Autodesk Inventor part; units mm, degrees
(part 2 of 2)
  line L179 (40.3047, 40.3055) -> (37.6531, 37.6538) construction
  line L180 (41.5531, 43.3) -> (40.3047, 40.3055) construction
  line L181 (39.7206, 44.9869) -> (41.5531, 43.3) construction
  line L182 (36.8395, 43.4955) -> (39.7206, 44.9869) construction
  line L183 (34.4158, 40.6339) -> (36.8395, 43.4955) construction
  arc A254 (34.4158, 40.6339) -> (30.9419, 43.3377) centre (0, 0) ccw construction
  line L184 (33.121, 46.3897) -> (30.9419, 43.3377) construction
  line L185 (33.8595, 49.5488) -> (33.121, 46.3897) construction
  line L186 (31.7743, 50.9111) -> (33.8595, 49.5488) construction
  line L187 (29.1779, 48.9658) -> (31.7743, 50.9111) construction
  line L188 (27.2583, 45.7444) -> (29.1779, 48.9658) construction
  arc A255 (27.2583, 45.7444) -> (23.3868, 47.8395) centre (0, 0) ccw construction
  line L189 (25.0337, 51.2085) -> (23.3868, 47.8395) construction
  line L190 (25.2422, 54.4461) -> (25.0337, 51.2085) construction
  line L191 (22.9612, 55.4467) -> (25.2422, 54.4461) construction
  line L192 (20.7204, 53.1005) -> (22.9612, 55.4467) construction
  line L193 (19.3573, 49.607) -> (20.7204, 53.1005) construction
  arc A256 (19.3573, 49.607) -> (15.1937, 51.0364) centre (0, 0) ccw construction
  line L194 (16.2637, 54.6305) -> (15.1937, 51.0364) construction
  line L195 (15.9364, 57.8583) -> (16.2637, 54.6305) construction
  line L196 (13.5219, 58.4697) -> (15.9364, 57.8583) construction
  line L197 (11.6978, 55.7868) -> (13.5219, 58.4697) construction
  line L198 (10.9282, 52.1166) -> (11.6978, 55.7868) construction
  arc A257 (10.9282, 52.1166) -> (6.5861, 52.8411) centre (0, 0) ccw construction
  line L199 (7.05, 56.5623) -> (6.5861, 52.8411) construction
  line L200 (6.1959, 59.6922) -> (7.05, 56.5623) construction
  line L201 (3.7136, 59.8979) -> (6.1959, 59.6922) construction
  line L202 (2.356, 56.9513) -> (3.7136, 59.8979) construction
  line L203 (2.201, 53.2045) -> (2.356, 56.9513) construction
  arc A258 (2.201, 53.2045) -> (-2.201, 53.2045) centre (0, 0) ccw construction
  line L204 (-2.356, 56.9513) -> (-2.201, 53.2045) construction
  line L205 (-3.7136, 59.8979) -> (-2.356, 56.9513) construction
  line L206 (-6.1959, 59.6922) -> (-3.7136, 59.8979) construction
  line L207 (-7.05, 56.5623) -> (-6.1959, 59.6922) construction
  line L208 (-6.5861, 52.8411) -> (-7.05, 56.5623) construction
  arc A259 (-6.5861, 52.8411) -> (-10.9282, 52.1166) centre (0, 0) ccw construction
  line L209 (-11.6978, 55.7868) -> (-10.9282, 52.1166) construction
  line L210 (-13.5219, 58.4697) -> (-11.6978, 55.7868) construction
  line L211 (-15.9364, 57.8583) -> (-13.5219, 58.4697) construction
  line L212 (-16.2637, 54.6305) -> (-15.9364, 57.8583) construction
  line L213 (-15.1937, 51.0364) -> (-16.2637, 54.6305) construction
  arc A260 (-15.1937, 51.0364) -> (-19.3573, 49.607) centre (0, 0) ccw construction
  line L214 (-20.7204, 53.1005) -> (-19.3573, 49.607) construction
  line L215 (-22.9612, 55.4467) -> (-20.7204, 53.1005) construction
  line L216 (-25.2422, 54.4461) -> (-22.9612, 55.4467) construction
  line L217 (-25.0337, 51.2085) -> (-25.2422, 54.4461) construction
  line L218 (-23.3868, 47.8395) -> (-25.0337, 51.2085) construction
  arc A261 (-23.3868, 47.8395) -> (-27.2583, 45.7444) centre (0, 0) ccw construction
  line L219 (-29.1779, 48.9658) -> (-27.2583, 45.7444) construction
  line L220 (-31.7743, 50.9111) -> (-29.1779, 48.9658) construction
  line L221 (-33.8595, 49.5488) -> (-31.7743, 50.9111) construction
  line L222 (-33.121, 46.3897) -> (-33.8595, 49.5488) construction
  line L223 (-30.9419, 43.3377) -> (-33.121, 46.3897) construction
  arc A262 (-30.9419, 43.3377) -> (-34.4158, 40.6339) centre (0, 0) ccw construction
  line L224 (-36.8395, 43.4955) -> (-34.4158, 40.6339) construction
  line L225 (-39.7206, 44.9869) -> (-36.8395, 43.4955) construction
  line L226 (-41.5531, 43.3) -> (-39.7206, 44.9869) construction
  line L227 (-40.3047, 40.3055) -> (-41.5531, 43.3) construction
  line L228 (-37.6531, 37.6538) -> (-40.3047, 40.3055) construction
  arc A263 (-37.6531, 37.6538) -> (-40.6345, 34.4151) centre (0, 0) ccw construction
  line L229 (-43.4961, 36.8387) -> (-40.6345, 34.4151) construction
  line L230 (-46.5835, 37.8355) -> (-43.4961, 36.8387) construction
  line L231 (-48.1134, 35.87) -> (-46.5835, 37.8355) construction
  line L232 (-46.3891, 33.1218) -> (-48.1134, 35.87) construction
  line L233 (-43.3372, 30.9427) -> (-46.3891, 33.1218) construction
  arc A264 (-43.3372, 30.9427) -> (-45.7449, 27.2575) centre (0, 0) ccw construction
  line L234 (-48.9663, 29.177) -> (-45.7449, 27.2575) construction
  line L235 (-52.1757, 29.6521) -> (-48.9663, 29.177) construction
  line L236 (-53.3612, 27.4616) -> (-52.1757, 29.6521) construction
  line L237 (-51.2081, 25.0347) -> (-53.3612, 27.4616) construction
  line L238 (-47.8391, 23.3877) -> (-51.2081, 25.0347) construction
  arc A265 (-47.8391, 23.3877) -> (-49.6074, 19.3563) centre (0, 0) ccw construction
  line L239 (-53.1009, 20.7195) -> (-49.6074, 19.3563) construction
  line L240 (-56.3447, 20.6599) -> (-53.1009, 20.7195) construction
  line L241 (-57.1534, 18.3041) -> (-56.3447, 20.6599) construction
  line L242 (-54.6302, 16.2647) -> (-57.1534, 18.3041) construction
  line L243 (-51.0361, 15.1946) -> (-54.6302, 16.2647) construction
  arc A266 (-51.0361, 15.1946) -> (-52.1168, 10.9272) centre (0, 0) ccw construction
  line L244 (-55.787, 11.6968) -> (-52.1168, 10.9272) construction
  line L245 (-58.9767, 11.1041) -> (-55.787, 11.6968) construction
  line L246 (-59.3867, 8.6473) -> (-58.9767, 11.1041) construction
  line L247 (-56.5622, 7.051) -> (-59.3867, 8.6473) construction
  line L248 (-16.4385, -43.0679) -> (-6.3271, -20.3574) construction
  arc A267 (-2.5, -21.1708) -> (-6.3271, -20.3574) centre (-4.5, -21.1708) ccw construction
  line L249 (-2.5, -21.1708) -> (-2.5, -46.0306) construction
  arc A268 (-4.6946, -48.0211) -> (-2.5, -46.0306) centre (-4.5, -46.0306) ccw construction
  arc A269 (-15.2432, -45.7789) -> (-4.6946, -48.0211) centre (0, 0) ccw construction
  arc A270 (-16.4385, -43.0679) -> (-15.2432, -45.7789) centre (-14.6114, -43.8813) ccw construction
  circle A271 centre (0, 0) radius 11 construction
  circle A272 centre (0, 0) radius 11
  constraints: 1 centre point, 1 coincident, 1 concentric
extrude "押し出し5" add sketch "スケッチ5" against normal up to surface (5.5 mm away) contours A272
equation "\"BendRadius\" = Thickness"
equation "\"BendReliefWidth\" = Thickness"
equation "\"BendReliefDepth\" = 0.5 * Thickness"
equation "\"CornerReliefSize\" = 4 * Thickness"
equation "\"MinimumRemnant\" = 2 * Thickness"
equation "\"TransitionRadius\" = BendRadius"
equation "\"JacobiRadiusSize\" = BendRadius"
equation "\"GapSize\" = Thickness"
equation "\"Thickness\" = 3.048"
